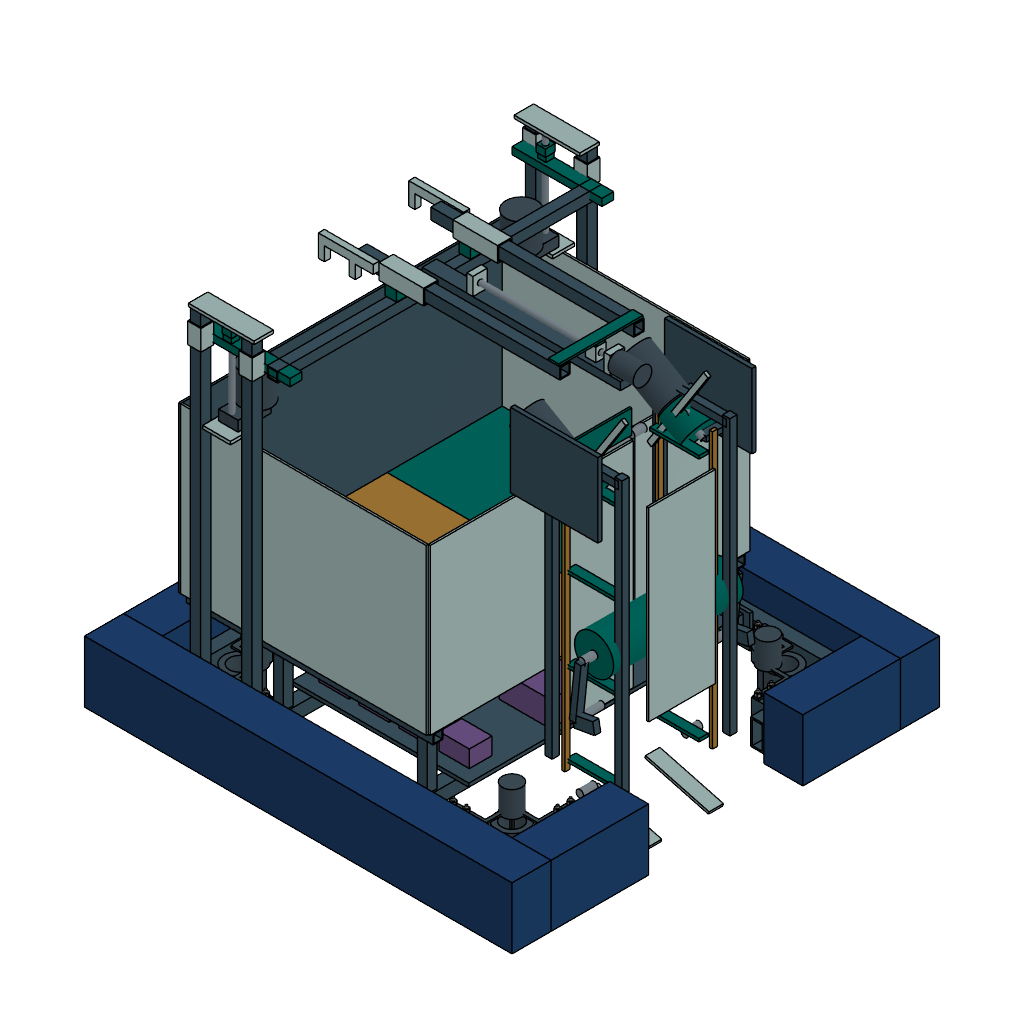
foundation-student (Autodesk Fusion 360 design; units mm, degrees)
part number: 2026-11-19-16-29-23-322
part number: 2026-11-19-16-29-24-588
part number: 2026-11-19-16-29-24-784
part number: 2026-11-19-16-29-24-907
part number: 2026-11-19-16-29-25-042
part number: 2026-11-19-16-29-25-132
part number: 2026-11-19-16-29-25-265
part number: 2026-11-19-16-29-25-401
part number: 2026-11-19-16-29-25-469
part number: 2026-11-19-16-29-25-542
part number: 2026-11-19-16-29-25-656
part number: 2026-11-19-16-29-25-749
part number: 2026-11-19-16-29-25-845
part number: 2026-11-19-16-29-25-954
part number: 2026-11-19-16-29-26-045
part number: 2026-11-19-16-29-26-140
part number: 2026-11-19-16-29-26-293
part number: 2026-11-19-16-29-26-432
part number: 2026-11-19-16-29-26-578
part number: 2026-11-19-16-29-26-718
part number: 2026-11-19-16-29-26-822
part number: 2026-11-19-16-29-26-924
part number: 2026-11-19-16-29-27-036
part number: 2026-11-19-16-29-27-164
part number: 2026-11-19-16-29-27-300
part number: 2026-11-19-16-29-27-426
part number: 2026-11-19-16-29-27-574
part number: 2026-11-19-16-29-27-708
part number: 2026-11-19-16-29-27-854
part number: 2026-11-19-16-29-28-022
part number: 2026-11-19-16-29-28-199
part number: 2026-11-19-16-29-28-361
part number: 2026-11-19-16-29-28-554
part number: 2026-11-19-16-29-28-745
part number: 2026-11-19-16-29-28-971
part number: 2026-11-19-16-29-29-160
part number: 2026-11-19-16-29-29-332
part number: 2026-11-19-16-29-29-497
part number: 2026-11-19-16-29-29-671
part number: 2026-11-19-16-29-29-862
part number: 2026-11-19-16-29-30-045
part number: 2026-11-19-16-29-30-240
part number: 2026-11-19-16-29-30-437
part number: 2026-11-19-16-29-30-622
part number: 2026-11-19-16-29-30-814
part number: 2026-11-19-16-29-30-996
part number: 2026-11-19-16-29-31-190
part number: 2026-11-19-16-29-31-381
part number: 2026-11-19-16-29-31-561
part number: 2026-11-19-16-29-31-741
part number: 2026-11-19-16-29-31-940
part number: 2026-11-19-16-29-32-174
part number: 2026-11-19-16-29-32-422
part number: 2026-11-19-16-29-32-619
part number: 2026-11-19-16-29-32-874
part number: 2026-11-19-16-29-33-099
part number: 2026-11-19-16-29-33-310
part number: 2026-11-19-16-29-33-534
part number: 2026-11-19-16-29-33-739
part number: 2026-11-19-16-29-33-957
part number: 2026-11-19-16-29-34-203
part number: 2026-11-19-16-29-34-447
part number: 2026-11-19-16-29-34-700
part number: 2026-11-19-16-29-34-969
part number: 2026-11-19-16-29-35-219
part number: 2026-11-19-16-29-35-475
part number: 2026-11-19-16-29-35-707
part number: 2026-11-19-16-29-35-952
part number: 2026-11-19-16-29-36-206
part number: 2026-11-19-16-29-36-472
part number: 2026-11-19-16-29-36-729
part number: 2026-11-19-16-29-37-001
part number: 2026-11-19-16-29-37-335
part number: 2026-11-19-16-29-37-615
part number: 2026-11-19-16-29-37-909
part number: 2026-11-19-16-29-38-228
part number: 2026-11-19-16-29-38-498
part number: 2026-11-19-16-29-38-772
part number: 2026-11-19-16-29-39-047
part number: 2026-11-19-16-29-39-326
part number: 2026-11-19-16-29-39-636
part number: 2026-11-19-16-29-40-074
part number: 2026-11-19-16-29-40-446
part number: 2026-11-19-16-29-40-762
part number: 2026-11-19-16-29-41-087
part number: 2026-11-19-16-29-41-429
part number: 2026-11-19-16-29-41-755
part number: 2026-11-19-16-29-42-071
part number: 2026-11-19-16-29-42-409
part number: 2026-11-19-16-29-42-776
part number: 2026-11-19-16-29-43-128
part number: 2026-11-19-16-29-43-473
part number: 2026-11-19-16-29-43-827
part number: 2026-11-19-16-29-44-180
part number: 2026-11-19-16-29-44-578
part number: 2026-11-19-16-29-44-987
part number: 2026-11-19-16-29-45-341
part number: 2026-11-19-16-29-45-728
part number: 2026-11-19-16-29-46-163
part number: 2026-11-19-16-29-46-577
part number: 2026-11-19-16-29-46-997
part number: 2026-11-19-16-29-47-400
part number: 2026-11-19-16-29-47-870
part number: 2026-11-19-16-29-48-379
part number: 2026-11-19-16-29-49-021
part number: 2026-11-19-16-29-49-607
part number: 2026-11-19-16-29-50-127
part number: 2026-11-19-16-29-50-624
part number: 2026-11-19-16-29-51-184
part number: 2026-11-19-16-29-51-808
part number: 2026-11-19-16-29-52-316
part number: 2026-11-19-16-29-52-811
part number: 2026-11-19-16-29-53-296
part number: 2026-11-19-16-29-53-786
part number: 2026-11-19-16-29-54-269
part number: 2026-11-19-16-29-54-713
part number: 2026-11-19-16-39-44-124
part number: 2026-11-19-16-39-44-486
part number: 2026-11-19-20-49-53-199
part number: 2026-11-19-20-49-53-588
part number: 2026-11-19-20-49-54-024
part number: 2026-11-19-20-49-54-407
part number: 2026-11-19-20-49-54-728
part number: 2026-11-19-20-49-55-064
part number: 2026-11-19-20-49-55-386
part number: 2026-11-19-20-49-55-703
part number: 2026-11-19-20-49-56-014
part number: 2026-11-19-20-49-56-330
part number: 2026-11-19-20-49-56-640
part number: 2026-11-19-20-49-56-959
part number: 2026-11-19-20-49-57-289
part number: 2026-11-19-20-49-57-613
part number: 2026-11-19-20-49-57-921
part number: 2026-11-19-20-49-58-244
part number: 2026-11-19-20-49-58-715
part number: 2026-11-19-20-49-59-050
part number: 2026-11-19-20-49-59-390
part number: 2026-11-19-20-49-59-708
part number: 2026-11-19-20-50-00-036
part number: 2026-11-19-20-50-00-368
part number: 2026-11-19-20-50-00-706
part number: 2026-11-19-20-50-01-053
part number: 2026-11-19-20-50-01-432
part number: 2026-11-19-20-50-01-806
part number: 2026-11-19-20-50-02-178
part number: 2026-11-19-20-50-02-582
part number: 2026-11-19-20-50-03-000
part number: 2026-11-19-20-50-03-410
part number: 2026-11-19-20-50-03-781
part number: 2026-11-19-20-50-04-185
part number: 2026-11-19-20-50-04-759
part number: 2026-11-19-20-50-05-171
part number: 2026-11-19-20-50-05-563
part number: 2026-11-19-20-50-05-945
part number: 2026-11-19-20-50-06-361
part number: 2026-11-19-20-50-06-774
part number: 2026-11-19-20-50-07-168
part number: 2026-11-19-20-50-07-583
part number: 2026-11-19-20-50-07-988
part number: 2026-11-19-20-50-08-402
part number: 2026-11-20-00-12-03-179
part number: 2026-11-20-00-12-05-400
part number: 2026-11-20-00-12-12-229
part number: 2026-11-20-00-12-13-884
part number: 2026-11-20-00-14-19-615
part number: 2026-11-20-00-14-22-937
part number: 2026-11-20-00-14-31-557
part number: 2026-11-20-00-14-34-829
part number: 2026-11-20-00-14-43-622
part number: 2026-11-20-00-14-52-118
part number: 2026-11-20-00-14-56-770
part number: 2026-11-20-00-15-06-271
part number: 2026-11-20-00-15-10-896
part number: 2026-11-20-00-15-14-635
part number: 2026-11-20-00-15-23-482
part number: 2026-11-20-00-15-27-004
part number: 2026-11-20-00-15-36-009
part number: 2026-11-20-00-15-45-151
part number: 2026-11-20-00-15-49-162
part number: 2026-11-20-00-15-57-500
part number: 2026-11-20-00-16-01-967
part number: 2026-11-20-00-16-05-799
part number: 2026-11-20-00-16-15-084
part number: 2026-11-20-00-16-19-187
part number: 2026-11-20-00-16-29-717
part number: 2026-11-20-00-16-41-609
part number: 2026-11-20-00-16-46-531
part number: 2026-11-20-00-16-56-596
part number: 2026-11-20-00-17-02-755
part number: 2026-11-20-00-17-07-080
part number: 2026-11-20-00-17-18-326
part number: 2026-11-20-00-17-23-572
part number: 2026-11-20-00-17-36-294
part number: 2026-11-20-00-17-48-159
part number: 2026-11-20-00-17-54-544
part number: 2026-11-20-00-18-05-921
part number: 2026-11-20-00-18-11-516
part number: 2026-11-20-00-18-15-728
part number: 2026-11-20-00-18-26-853
part number: 2026-11-20-00-18-31-111
part number: 2026-11-20-00-18-43-909
part number: 2026-11-20-00-18-56-145
part number: 2026-11-20-00-19-02-507
part number: 2026-11-20-00-19-14-913
part number: 2026-11-20-00-19-20-927
part number: 2026-11-20-00-19-26-560
part number: 2026-11-20-00-19-39-179
part number: 2026-11-20-00-19-43-997
part number: 2026-11-20-00-19-56-769
part number: 2026-11-20-00-20-10-561
part number: 2026-11-20-00-20-16-618
part number: 2026-11-20-00-20-31-020
part number: 2026-11-20-00-20-37-639
part number: 2026-11-20-00-20-43-429
part number: 2026-11-20-00-20-56-687
part number: 2026-11-20-00-21-02-006
part number: 2026-11-20-00-21-15-677
part number: 2026-11-20-00-21-30-158
part number: 2026-11-20-00-21-37-869
part number: 2026-11-20-00-21-53-268
part number: 2026-11-20-00-22-00-849
part number: 2026-11-20-00-22-06-838
part number: 2026-11-20-00-22-22-480
part number: 2026-11-20-00-22-28-660
part number: 2026-11-20-00-22-48-711
part number: 2026-11-20-00-23-07-970
part number: 2026-11-20-00-23-16-941
part number: 2026-11-20-00-23-37-375
part number: 2026-11-20-00-25-41-586
part number: 2026-11-20-00-26-13-050
part number: 2026-11-20-00-28-41-417
part number: 2026-11-20-00-29-10-943
part number: 2026-11-20-00-32-07-156
part number: 2026-11-20-00-32-46-030
part number: 2026-11-20-00-35-42-419
part number: 2026-11-20-00-36-22-594
Autodesk Fusion 360 part; units mm, degrees
(part 1 of 7)
sketch "Editable cross section" plane through (0, 0, 0) normal (0, 0, 1) x (1, 0, 0) in component "left perimeter tube"
  line L0 (-12.7, -25.4) -> (12.7, -25.4)
  line L1 (12.7, -25.4) -> (12.7, 25.4)
  line L2 (12.7, 25.4) -> (-12.7, 25.4)
  line L3 (-12.7, 25.4) -> (-12.7, -25.4)
  line L4 (-10.16, -22.86) -> (10.16, -22.86)
  line L5 (10.16, -22.86) -> (10.16, 22.86)
  line L6 (10.16, 22.86) -> (-10.16, 22.86)
  line L7 (-10.16, 22.86) -> (-10.16, -22.86)
sketch "Editable cross section (2)" plane through (0, 0, 0) normal (0, 0, 1) x (1, 0, 0) in component "left front return"
  line L0 (-12.7, -25.4) -> (12.7, -25.4)
  line L1 (12.7, -25.4) -> (12.7, 25.4)
  line L2 (12.7, 25.4) -> (-12.7, 25.4)
  line L3 (-12.7, 25.4) -> (-12.7, -25.4)
  line L4 (-10.16, -22.86) -> (10.16, -22.86)
  line L5 (10.16, -22.86) -> (10.16, 22.86)
  line L6 (10.16, 22.86) -> (-10.16, 22.86)
  line L7 (-10.16, 22.86) -> (-10.16, -22.86)
sketch "Editable cross section (3)" plane through (0, 0, 0) normal (0, 0, 1) x (1, 0, 0) in component "left blue side bumper"
  line L0 (-416, -38) -> (416, -38)
  line L1 (416, -38) -> (416, 38)
  line L2 (416, 38) -> (-416, 38)
  line L3 (-416, 38) -> (-416, -38)
extrude "Stock length" add sketch "Editable cross section (3)" along normal blind 120 makes body 1 in component "left blue side bumper"
sketch "Editable cross section (4)" plane through (0, 0, 0) normal (0, 0, 1) x (1, 0, 0) in component "left blue front bumper"
  line L0 (-38, -95) -> (38, -95)
  line L1 (38, -95) -> (38, 95)
  line L2 (38, 95) -> (-38, 95)
  line L3 (-38, 95) -> (-38, -95)
extrude "Stock length'" add sketch "Editable cross section (4)" along normal blind 120 separate body makes body 2 in component "left blue front bumper"
sketch "Editable cross section (5)" plane through (0, 0, 0) normal (0, 0, 1) x (1, 0, 0) in component "right perimeter tube"
  line L0 (-12.7, -25.4) -> (12.7, -25.4)
  line L1 (12.7, -25.4) -> (12.7, 25.4)
  line L2 (12.7, 25.4) -> (-12.7, 25.4)
  line L3 (-12.7, 25.4) -> (-12.7, -25.4)
  line L4 (-10.16, -22.86) -> (10.16, -22.86)
  line L5 (10.16, -22.86) -> (10.16, 22.86)
  line L6 (10.16, 22.86) -> (-10.16, 22.86)
  line L7 (-10.16, 22.86) -> (-10.16, -22.86)
sketch "Editable cross section (6)" plane through (0, 0, 0) normal (0, 0, 1) x (1, 0, 0) in component "right front return"
  line L0 (-12.7, -25.4) -> (12.7, -25.4)
  line L1 (12.7, -25.4) -> (12.7, 25.4)
  line L2 (12.7, 25.4) -> (-12.7, 25.4)
  line L3 (-12.7, 25.4) -> (-12.7, -25.4)
  line L4 (-10.16, -22.86) -> (10.16, -22.86)
  line L5 (10.16, -22.86) -> (10.16, 22.86)
  line L6 (10.16, 22.86) -> (-10.16, 22.86)
  line L7 (-10.16, 22.86) -> (-10.16, -22.86)
sketch "Editable cross section (7)" plane through (0, 0, 0) normal (0, 0, 1) x (1, 0, 0) in component "right blue side bumper"
  line L0 (-416, -38) -> (416, -38)
  line L1 (416, -38) -> (416, 38)
  line L2 (416, 38) -> (-416, 38)
  line L3 (-416, 38) -> (-416, -38)
extrude "Stock length''" add sketch "Editable cross section (7)" along normal blind 120 separate body makes body 3 in component "right blue side bumper"
sketch "Editable cross section (8)" plane through (0, 0, 0) normal (0, 0, 1) x (1, 0, 0) in component "right blue front bumper"
  line L0 (-38, -95) -> (38, -95)
  line L1 (38, -95) -> (38, 95)
  line L2 (38, 95) -> (-38, 95)
  line L3 (-38, 95) -> (-38, -95)
extrude "Stock length'''" add sketch "Editable cross section (8)" along normal blind 120 separate body makes body 4 in component "right blue front bumper"
sketch "Editable cross section (9)" plane through (0, 0, 0) normal (0, 0, 1) x (1, 0, 0) in component "rear perimeter tube"
  line L0 (-12.7, -25.4) -> (12.7, -25.4)
  line L1 (12.7, -25.4) -> (12.7, 25.4)
  line L2 (12.7, 25.4) -> (-12.7, 25.4)
  line L3 (-12.7, 25.4) -> (-12.7, -25.4)
  line L4 (-10.16, -22.86) -> (10.16, -22.86)
  line L5 (10.16, -22.86) -> (10.16, 22.86)
  line L6 (10.16, 22.86) -> (-10.16, 22.86)
  line L7 (-10.16, 22.86) -> (-10.16, -22.86)
sketch "Editable cross section (10)" plane through (0, 0, 0) normal (0, 0, 1) x (1, 0, 0) in component "rear blue bumper"
  line L0 (-38, -340) -> (38, -340)
  line L1 (38, -340) -> (38, 340)
  line L2 (38, 340) -> (-38, 340)
  line L3 (-38, 340) -> (-38, -340)
extrude "Stock length''''" add sketch "Editable cross section (10)" along normal blind 120 separate body makes body 5 in component "rear blue bumper"
sketch "Editable cross section (11)" plane through (0, 0, 0) normal (0, 0, 1) x (1, 0, 0) in component "front left module tab spacer 1"
  line L0 (-18.5, -11.55) -> (18.5, -11.55)
  line L1 (18.5, -11.55) -> (18.5, 11.55)
  line L2 (18.5, 11.55) -> (-18.5, 11.55)
  line L3 (-18.5, 11.55) -> (-18.5, -11.55)
  circle A0 centre (12.85, -3.3) radius 2.65
  circle A1 centre (-12.55, -3.3) radius 2.65
sketch "Editable cross section (12)" plane through (0, 0, 0) normal (0, 0, 1) x (1, 0, 0) in component "front left module tab spacer 2"
  line L0 (-11.55, -18.5) -> (11.55, -18.5)
  line L1 (11.55, -18.5) -> (11.55, 18.5)
  line L2 (11.55, 18.5) -> (-11.55, 18.5)
  line L3 (-11.55, 18.5) -> (-11.55, -18.5)
  circle A0 centre (-3.3, 12.85) radius 2.65
  circle A1 centre (-3.3, -12.55) radius 2.65
sketch "Editable cross section (13)" plane through (0, 0, 0) normal (0, 0, 1) x (1, 0, 0) in component "front right module tab spacer 1"
  line L0 (-11.55, -18.5) -> (11.55, -18.5)
  line L1 (11.55, -18.5) -> (11.55, 18.5)
  line L2 (11.55, 18.5) -> (-11.55, 18.5)
  line L3 (-11.55, 18.5) -> (-11.55, -18.5)
  circle A0 centre (-3.3, -12.85) radius 2.65
  circle A1 centre (-3.3, 12.55) radius 2.65
sketch "Editable cross section (14)" plane through (0, 0, 0) normal (0, 0, 1) x (1, 0, 0) in component "front right module tab spacer 2"
  line L0 (-18.5, -11.55) -> (18.5, -11.55)
  line L1 (18.5, -11.55) -> (18.5, 11.55)
  line L2 (18.5, 11.55) -> (-18.5, 11.55)
  line L3 (-18.5, 11.55) -> (-18.5, -11.55)
  circle A0 centre (12.85, 3.3) radius 2.65
  circle A1 centre (-12.55, 3.3) radius 2.65
sketch "Editable cross section (15)" plane through (0, 0, 0) normal (0, 0, 1) x (1, 0, 0) in component "rear left module tab spacer 1"
  line L0 (-11.55, -18.5) -> (11.55, -18.5)
  line L1 (11.55, -18.5) -> (11.55, 18.5)
  line L2 (11.55, 18.5) -> (-11.55, 18.5)
  line L3 (-11.55, 18.5) -> (-11.55, -18.5)
  circle A0 centre (3.3, 12.85) radius 2.65
  circle A1 centre (3.3, -12.55) radius 2.65
sketch "Editable cross section (16)" plane through (0, 0, 0) normal (0, 0, 1) x (1, 0, 0) in component "rear left module tab spacer 2"
  line L0 (-18.5, -11.55) -> (18.5, -11.55)
  line L1 (18.5, -11.55) -> (18.5, 11.55)
  line L2 (18.5, 11.55) -> (-18.5, 11.55)
  line L3 (-18.5, 11.55) -> (-18.5, -11.55)
  circle A0 centre (-12.85, -3.3) radius 2.65
  circle A1 centre (12.55, -3.3) radius 2.65
sketch "Editable cross section (17)" plane through (0, 0, 0) normal (0, 0, 1) x (1, 0, 0) in component "rear right module tab spacer 1"
  line L0 (-18.5, -11.55) -> (18.5, -11.55)
  line L1 (18.5, -11.55) -> (18.5, 11.55)
  line L2 (18.5, 11.55) -> (-18.5, 11.55)
  line L3 (-18.5, 11.55) -> (-18.5, -11.55)
  circle A0 centre (-12.85, 3.3) radius 2.65
  circle A1 centre (12.55, 3.3) radius 2.65
sketch "Editable cross section (18)" plane through (0, 0, 0) normal (0, 0, 1) x (1, 0, 0) in component "rear right module tab spacer 2"
  line L0 (-11.55, -18.5) -> (11.55, -18.5)
  line L1 (11.55, -18.5) -> (11.55, 18.5)
  line L2 (11.55, 18.5) -> (-11.55, 18.5)
  line L3 (-11.55, 18.5) -> (-11.55, -18.5)
  circle A0 centre (3.3, -12.85) radius 2.65
  circle A1 centre (3.3, 12.55) radius 2.65
sketch "Editable cross section (19)" plane through (0, 0, 0) normal (0, 0, 1) x (1, 0, 0) in component "rear right hopper post"
  line L0 (-10, -8) -> (10, -8)
  line L1 (10, -8) -> (10, 8)
  line L2 (10, 8) -> (-10, 8)
  line L3 (-10, 8) -> (-10, -8)
sketch "Editable cross section (20)" plane through (0, 0, 0) normal (0, 0, 1) x (1, 0, 0) in component "front right hopper post"
  line L0 (-10, -8) -> (10, -8)
  line L1 (10, -8) -> (10, 8)
  line L2 (10, 8) -> (-10, 8)
  line L3 (-10, 8) -> (-10, -8)
sketch "Editable cross section (21)" plane through (0, 0, 0) normal (0, 0, 1) x (1, 0, 0) in component "right floor sill"
  line L0 (-9, -6) -> (9, -6)
  line L1 (9, -6) -> (9, 6)
  line L2 (9, 6) -> (-9, 6)
  line L3 (-9, 6) -> (-9, -6)
sketch "Editable cross section (22)" plane through (0, 0, 0) normal (0, 0, 1) x (1, 0, 0) in component "rear left hopper post"
  line L0 (-10, -8) -> (10, -8)
  line L1 (10, -8) -> (10, 8)
  line L2 (10, 8) -> (-10, 8)
  line L3 (-10, 8) -> (-10, -8)
sketch "Editable cross section (23)" plane through (0, 0, 0) normal (0, 0, 1) x (1, 0, 0) in component "front left hopper post"
  line L0 (-10, -8) -> (10, -8)
  line L1 (10, -8) -> (10, 8)
  line L2 (10, 8) -> (-10, 8)
  line L3 (-10, 8) -> (-10, -8)
sketch "Editable cross section (24)" plane through (0, 0, 0) normal (0, 0, 1) x (1, 0, 0) in component "left floor sill"
  line L0 (-9, -6) -> (9, -6)
  line L1 (9, -6) -> (9, 6)
  line L2 (9, 6) -> (-9, 6)
  line L3 (-9, 6) -> (-9, -6)
sketch "Editable cross section (25)" plane through (0, 0, 0) normal (0, 0, 1) x (1, 0, 0) in component "rear deck crossmember"
  line L0 (-10, -12.5) -> (10, -12.5)
  line L1 (10, -12.5) -> (10, 12.5)
  line L2 (10, 12.5) -> (-10, 12.5)
  line L3 (-10, 12.5) -> (-10, -12.5)
sketch "Editable cross section (26)" plane through (0, 0, 0) normal (0, 0, 1) x (1, 0, 0) in component "front deck crossmember"
  line L0 (-10, -12.5) -> (10, -12.5)
  line L1 (10, -12.5) -> (10, 12.5)
  line L2 (10, 12.5) -> (-10, 12.5)
  line L3 (-10, 12.5) -> (-10, -12.5)
sketch "Editable cross section (27)" plane through (0, 0, 0) normal (0, 0, 1) x (1, 0, 0) in component "left electronics deck"
  line L0 (-172.5, -102) -> (172.5, -102)
  line L1 (172.5, -102) -> (172.5, 102)
  line L2 (172.5, 102) -> (-172.5, 102)
  line L3 (-172.5, 102) -> (-172.5, -102)
extrude "Stock length'''''" add sketch "Editable cross section (27)" along normal blind 7 separate body makes body 6 in component "left electronics deck"
sketch "Editable cross section (28)" plane through (0, 0, 0) normal (0, 0, 1) x (1, 0, 0) in component "right electronics deck"
  line L0 (-172.5, -103.5) -> (172.5, -103.5)
  line L1 (172.5, -103.5) -> (172.5, 103.5)
  line L2 (172.5, 103.5) -> (-172.5, 103.5)
  line L3 (-172.5, 103.5) -> (-172.5, -103.5)
extrude "Stock length''''''" add sketch "Editable cross section (28)" along normal blind 7 separate body makes body 7 in component "right electronics deck"
sketch "Editable cross section (29)" plane through (0, 0, 0) normal (0, 0, 1) x (1, 0, 0) in component "fore electronics deck bridge"
  line L0 (-56.5, -45.5) -> (56.5, -45.5)
  line L1 (56.5, -45.5) -> (56.5, 45.5)
  line L2 (56.5, 45.5) -> (-56.5, 45.5)
  line L3 (-56.5, 45.5) -> (-56.5, -45.5)
extrude "Stock length'''''''" add sketch "Editable cross section (29)" along normal blind 7 separate body makes body 8 in component "fore electronics deck bridge"
sketch "Editable cross section (30)" plane through (0, 0, 0) normal (0, 0, 1) x (1, 0, 0) in component "aft electronics deck bridge"
  line L0 (-20.5, -45.5) -> (20.5, -45.5)
  line L1 (20.5, -45.5) -> (20.5, 45.5)
  line L2 (20.5, 45.5) -> (-20.5, 45.5)
  line L3 (-20.5, 45.5) -> (-20.5, -45.5)
extrude "Stock length''''''''" add sketch "Editable cross section (30)" along normal blind 7 separate body makes body 9 in component "aft electronics deck bridge"
sketch "Editable cross section (31)" plane through (0, 0, 0) normal (0, 0, 1) x (1, 0, 0) in component "battery cradle floor"
  line L0 (-95.5, -45.5) -> (95.5, -45.5)
  line L1 (95.5, -45.5) -> (95.5, 45.5)
  line L2 (95.5, 45.5) -> (-95.5, 45.5)
  line L3 (-95.5, 45.5) -> (-95.5, -45.5)
extrude "Stock length'''''''''" add sketch "Editable cross section (31)" along normal blind 4 separate body makes body 10 in component "battery cradle floor"
sketch "Editable cross section (32)" plane through (0, 0, 0) normal (0, 0, 1) x (1, 0, 0) in component "battery cradle wall -44"
  line L0 (-95.5, -2) -> (95.5, -2)
  line L1 (95.5, -2) -> (95.5, 2)
  line L2 (95.5, 2) -> (-95.5, 2)
  line L3 (-95.5, 2) -> (-95.5, -2)
extrude "Stock length''''''''''" add sketch "Editable cross section (32)" along normal blind 81 separate body makes body 11 in component "battery cradle wall -44"
sketch "Editable cross section (33)" plane through (0, 0, 0) normal (0, 0, 1) x (1, 0, 0) in component "battery cradle wall 43"
  line L0 (-95.5, -2) -> (95.5, -2)
  line L1 (95.5, -2) -> (95.5, 2)
  line L2 (95.5, 2) -> (-95.5, 2)
  line L3 (-95.5, 2) -> (-95.5, -2)
extrude "Stock length'''''''''''" add sketch "Editable cross section (33)" along normal blind 81 separate body makes body 12 in component "battery cradle wall 43"
sketch "Editable cross section (34)" plane through (0, 0, 0) normal (0, 0, 1) x (1, 0, 0) in component "battery secured envelope"
  line L0 (-90.5, -38) -> (90.5, -38)
  line L1 (90.5, -38) -> (90.5, 38)
  line L2 (90.5, 38) -> (-90.5, 38)
  line L3 (-90.5, 38) -> (-90.5, -38)
extrude "Stock length''''''''''''" add sketch "Editable cross section (34)" along normal blind 167 separate body makes body 13 in component "battery secured envelope"
sketch "Editable cross section (35)" plane through (0, 0, 0) normal (0, 0, 1) x (1, 0, 0) in component "distribution enclosure reserve"
  line L0 (-50, -77) -> (50, -77)
  line L1 (50, -77) -> (50, 77)
  line L2 (50, 77) -> (-50, 77)
  line L3 (-50, 77) -> (-50, -77)
extrude "Stock length'''''''''''''" add sketch "Editable cross section (35)" along normal blind 49 separate body makes body 14 in component "distribution enclosure reserve"
sketch "Editable cross section (36)" plane through (0, 0, 0) normal (0, 0, 1) x (1, 0, 0) in component "robot controller reserve"
  line L0 (-83.5, -46) -> (83.5, -46)
  line L1 (83.5, -46) -> (83.5, 46)
  line L2 (83.5, 46) -> (-83.5, 46)
  line L3 (-83.5, 46) -> (-83.5, -46)
extrude "Stock length''''''''''''''" add sketch "Editable cross section (36)" along normal blind 42 separate body makes body 15 in component "robot controller reserve"
sketch "Editable cross section (37)" plane through (0, 0, 0) normal (0, 0, 1) x (1, 0, 0) in component "field radio reserve"
  line L0 (-64.5, -36.5) -> (64.5, -36.5)
  line L1 (64.5, -36.5) -> (64.5, 36.5)
  line L2 (64.5, 36.5) -> (-64.5, 36.5)
  line L3 (-64.5, 36.5) -> (-64.5, -36.5)
extrude "Stock length'''''''''''''''" add sketch "Editable cross section (37)" along normal blind 39 separate body makes body 16 in component "field radio reserve"
sketch "Editable cross section (38)" plane through (0, 0, 0) normal (0, 0, 1) x (1, 0, 0) in component "drive controller reserve 1"
  line L0 (-29.5, -22) -> (29.5, -22)
  line L1 (29.5, -22) -> (29.5, 22)
  line L2 (29.5, 22) -> (-29.5, 22)
  line L3 (-29.5, 22) -> (-29.5, -22)
extrude "Stock length''''''''''''''''" add sketch "Editable cross section (38)" along normal blind 33 separate body makes body 17 in component "drive controller reserve 1"
sketch "Editable cross section (39)" plane through (0, 0, 0) normal (0, 0, 1) x (1, 0, 0) in component "drive controller reserve 2"
  line L0 (-29.5, -22) -> (29.5, -22)
  line L1 (29.5, -22) -> (29.5, 22)
  line L2 (29.5, 22) -> (-29.5, 22)
  line L3 (-29.5, 22) -> (-29.5, -22)
extrude "Stock length'''''''''''''''''" add sketch "Editable cross section (39)" along normal blind 33 separate body makes body 18 in component "drive controller reserve 2"
sketch "Editable cross section (40)" plane through (0, 0, 0) normal (0, 0, 1) x (1, 0, 0) in component "drive controller reserve 3"
  line L0 (-29.5, -22) -> (29.5, -22)
  line L1 (29.5, -22) -> (29.5, 22)
  line L2 (29.5, 22) -> (-29.5, 22)
  line L3 (-29.5, 22) -> (-29.5, -22)
extrude "Stock length''''''''''''''''''" add sketch "Editable cross section (40)" along normal blind 33 separate body makes body 19 in component "drive controller reserve 3"
sketch "Editable cross section (41)" plane through (0, 0, 0) normal (0, 0, 1) x (1, 0, 0) in component "drive controller reserve 4"
  line L0 (-29.5, -22) -> (29.5, -22)
  line L1 (29.5, -22) -> (29.5, 22)
  line L2 (29.5, 22) -> (-29.5, 22)
  line L3 (-29.5, 22) -> (-29.5, -22)
extrude "Stock length'''''''''''''''''''" add sketch "Editable cross section (41)" along normal blind 33 separate body makes body 20 in component "drive controller reserve 4"
sketch "Editable cross section (42)" plane through (0, 0, 0) normal (0, 0, 1) x (1, 0, 0) in component "drive controller reserve 5"
  line L0 (-29.5, -22) -> (29.5, -22)
  line L1 (29.5, -22) -> (29.5, 22)
  line L2 (29.5, 22) -> (-29.5, 22)
  line L3 (-29.5, 22) -> (-29.5, -22)
extrude "Stock length''''''''''''''''''''" add sketch "Editable cross section (42)" along normal blind 33 separate body makes body 21 in component "drive controller reserve 5"
sketch "Editable cross section (43)" plane through (0, 0, 0) normal (0, 0, 1) x (1, 0, 0) in component "drive controller reserve 6"
  line L0 (-29.5, -22) -> (29.5, -22)
  line L1 (29.5, -22) -> (29.5, 22)
  line L2 (29.5, 22) -> (-29.5, 22)
  line L3 (-29.5, 22) -> (-29.5, -22)
extrude "Stock length'''''''''''''''''''''" add sketch "Editable cross section (43)" along normal blind 33 separate body makes body 22 in component "drive controller reserve 6"
sketch "Editable cross section (44)" plane through (0, 0, 0) normal (0, 0, 1) x (1, 0, 0) in component "drive controller reserve 7"
  line L0 (-29.5, -22) -> (29.5, -22)
  line L1 (29.5, -22) -> (29.5, 22)
  line L2 (29.5, 22) -> (-29.5, 22)
  line L3 (-29.5, 22) -> (-29.5, -22)
extrude "Stock length''''''''''''''''''''''" add sketch "Editable cross section (44)" along normal blind 33 separate body makes body 23 in component "drive controller reserve 7"
sketch "Editable cross section (45)" plane through (0, 0, 0) normal (0, 0, 1) x (1, 0, 0) in component "drive controller reserve 8"
  line L0 (-29.5, -22) -> (29.5, -22)
  line L1 (29.5, -22) -> (29.5, 22)
  line L2 (29.5, 22) -> (-29.5, 22)
  line L3 (-29.5, 22) -> (-29.5, -22)
extrude "Stock length'''''''''''''''''''''''" add sketch "Editable cross section (45)" along normal blind 33 separate body makes body 24 in component "drive controller reserve 8"
sketch "Editable cross section (46)" plane through (0, 0, 0) normal (0, 0, 1) x (1, 0, 0) in component "hopper back panel"
  line L0 (-2, -315) -> (2, -315)
  line L1 (2, -315) -> (2, 315)
  line L2 (2, 315) -> (-2, 315)
  line L3 (-2, 315) -> (-2, -315)
extrude "Stock length''''''''''''''''''''''''" add sketch "Editable cross section (46)" along normal blind 320 separate body makes body 25 in component "hopper back panel"
sketch "Editable cross section (47)" plane through (0, 0, 0) normal (0, 0, 1) x (1, 0, 0) in component "right hopper wall"
  line L0 (-239, -2) -> (239, -2)
  line L1 (239, -2) -> (239, 2)
  line L2 (239, 2) -> (-239, 2)
  line L3 (-239, 2) -> (-239, -2)
extrude "Stock length'''''''''''''''''''''''''" add sketch "Editable cross section (47)" along normal blind 320 separate body makes body 26 in component "right hopper wall"
sketch "Editable cross section (48)" plane through (0, 0, 0) normal (0, 0, 1) x (1, 0, 0) in component "right hopper front wing"
  line L0 (-2, -112) -> (2, -112)
  line L1 (2, -112) -> (2, 112)
  line L2 (2, 112) -> (-2, 112)
  line L3 (-2, 112) -> (-2, -112)
extrude "Stock length''''''''''''''''''''''''''" add sketch "Editable cross section (48)" along normal blind 320 separate body makes body 27 in component "right hopper front wing"
sketch "Editable cross section (49)" plane through (0, 0, 0) normal (0, 0, 1) x (1, 0, 0) in component "right cross feed deck"
  line L0 (-239, -112) -> (239, -112)
  line L1 (239, -112) -> (239, 112)
  line L2 (239, 112) -> (-239, 112)
  line L3 (-239, 112) -> (-239, -112)
extrude "Stock length'''''''''''''''''''''''''''" add sketch "Editable cross section (49)" along normal blind 5 separate body makes body 28 in component "right cross feed deck"
sketch "Editable cross section (50)" plane through (0, 0, 0) normal (0, 0, 1) x (1, 0, 0) in component "right front elevator upright"
  line L0 (-7, -7) -> (7, -7)
  line L1 (7, -7) -> (7, 7)
  line L2 (7, 7) -> (-7, 7)
  line L3 (-7, 7) -> (-7, -7)
extrude "Stock length''''''''''''''''''''''''''''" add sketch "Editable cross section (50)" along normal blind 537 separate body makes body 29 in component "right front elevator upright"
sketch "Editable cross section (51)" plane through (0, 0, 0) normal (0, 0, 1) x (1, 0, 0) in component "right rear elevator upright"
  line L0 (-7, -7) -> (7, -7)
  line L1 (7, -7) -> (7, 7)
  line L2 (7, 7) -> (-7, 7)
  line L3 (-7, 7) -> (-7, -7)
extrude "Stock length'''''''''''''''''''''''''''''" add sketch "Editable cross section (51)" along normal blind 535 separate body makes body 30 in component "right rear elevator upright"
sketch "Editable cross section (52)" plane through (0, 0, 0) normal (0, 0, 1) x (1, 0, 0) in component "right elevator upper tie"
  line L0 (-7, -7) -> (7, -7)
  line L1 (7, -7) -> (7, 7)
  line L2 (7, 7) -> (-7, 7)
  line L3 (-7, 7) -> (-7, -7)
extrude "Stock length''''''''''''''''''''''''''''''" add sketch "Editable cross section (52)" along normal blind 138 separate body makes body 31 in component "right elevator upper tie"
sketch "Editable cross section (53)" plane through (0, 0, 0) normal (0, 0, 1) x (1, 0, 0) in component "right inside lift belt"
  line L0 (-3, -5) -> (3, -5)
  line L1 (3, -5) -> (3, 5)
  line L2 (3, 5) -> (-3, 5)
  line L3 (-3, 5) -> (-3, -5)
extrude "Stock length'''''''''''''''''''''''''''''''" add sketch "Editable cross section (53)" along normal blind 535 separate body makes body 32 in component "right inside lift belt"
sketch "Editable cross section (54)" plane through (0, 0, 0) normal (0, 0, 1) x (1, 0, 0) in component "right outside lift belt"
  line L0 (-3, -5) -> (3, -5)
  line L1 (3, -5) -> (3, 5)
  line L2 (3, 5) -> (-3, 5)
  line L3 (-3, 5) -> (-3, -5)
extrude "Stock length''''''''''''''''''''''''''''''''" add sketch "Editable cross section (54)" along normal blind 535 separate body makes body 33 in component "right outside lift belt"
sketch "Editable cross section (55)" plane through (0, 0, 0) normal (0, 0, 1) x (1, 0, 0) in component "right lift shelf 1"
  line L0 (-48, -9) -> (48, -9)
  line L1 (48, -9) -> (48, 9)
  line L2 (48, 9) -> (-48, 9)
  line L3 (-48, 9) -> (-48, -9)
extrude "Stock length'''''''''''''''''''''''''''''''''" add sketch "Editable cross section (55)" along normal blind 6 separate body makes body 34 in component "right lift shelf 1"
sketch "Editable cross section (56)" plane through (0, 0, 0) normal (0, 0, 1) x (1, 0, 0) in component "right lift shelf 2"
  line L0 (-48, -9) -> (48, -9)
  line L1 (48, -9) -> (48, 9)
  line L2 (48, 9) -> (-48, 9)
  line L3 (-48, 9) -> (-48, -9)
extrude "Stock length''''''''''''''''''''''''''''''''''" add sketch "Editable cross section (56)" along normal blind 6 separate body makes body 35 in component "right lift shelf 2"
sketch "Editable cross section (57)" plane through (0, 0, 0) normal (0, 0, 1) x (1, 0, 0) in component "right lift shelf 3"
  line L0 (-48, -9) -> (48, -9)
  line L1 (48, -9) -> (48, 9)
  line L2 (48, 9) -> (-48, 9)
  line L3 (-48, 9) -> (-48, -9)
extrude "Stock length'''''''''''''''''''''''''''''''''''" add sketch "Editable cross section (57)" along normal blind 6 separate body makes body 36 in component "right lift shelf 3"
sketch "Editable cross section (58)" plane through (0, 0, 0) normal (0, 0, 1) x (1, 0, 0) in component "right lift shelf 4"
  line L0 (-48, -9) -> (48, -9)
  line L1 (48, -9) -> (48, 9)
  line L2 (48, 9) -> (-48, 9)
  line L3 (-48, 9) -> (-48, -9)
extrude "Stock length''''''''''''''''''''''''''''''''''''" add sketch "Editable cross section (58)" along normal blind 6 separate body makes body 37 in component "right lift shelf 4"
sketch "Editable cross section (59)" plane through (0, 0, 0) normal (0, 0, 1) x (1, 0, 0) in component "right intake ramp"
  line L0 (-14, -2.5) -> (14, -2.5)
  line L1 (14, -2.5) -> (14, 2.5)
  line L2 (14, 2.5) -> (-14, 2.5)
  line L3 (-14, 2.5) -> (-14, -2.5)
extrude "Stock length'''''''''''''''''''''''''''''''''''''" add sketch "Editable cross section (59)" along normal blind 128.316 separate body makes body 38 in component "right intake ramp"
sketch "Editable cross section (60)" plane through (0, 0, 0) normal (0, 0, 1) x (1, 0, 0) in component "left hopper wall"
  line L0 (-239, -2) -> (239, -2)
  line L1 (239, -2) -> (239, 2)
  line L2 (239, 2) -> (-239, 2)
  line L3 (-239, 2) -> (-239, -2)
extrude "Stock length''''''''''''''''''''''''''''''''''''''" add sketch "Editable cross section (60)" along normal blind 320 separate body makes body 39 in component "left hopper wall"
sketch "Editable cross section (61)" plane through (0, 0, 0) normal (0, 0, 1) x (1, 0, 0) in component "left hopper front wing"
  line L0 (-2, -112) -> (2, -112)
  line L1 (2, -112) -> (2, 112)
  line L2 (2, 112) -> (-2, 112)
  line L3 (-2, 112) -> (-2, -112)
extrude "Stock length'''''''''''''''''''''''''''''''''''''''" add sketch "Editable cross section (61)" along normal blind 320 separate body makes body 40 in component "left hopper front wing"
sketch "Editable cross section (62)" plane through (0, 0, 0) normal (0, 0, 1) x (1, 0, 0) in component "left cross feed deck"
  line L0 (-239, -112) -> (239, -112)
  line L1 (239, -112) -> (239, 112)
  line L2 (239, 112) -> (-239, 112)
  line L3 (-239, 112) -> (-239, -112)
extrude "Stock length''''''''''''''''''''''''''''''''''''''''" add sketch "Editable cross section (62)" along normal blind 5 separate body makes body 41 in component "left cross feed deck"
sketch "Editable cross section (63)" plane through (0, 0, 0) normal (0, 0, 1) x (1, 0, 0) in component "left front elevator upright"
  line L0 (-7, -7) -> (7, -7)
  line L1 (7, -7) -> (7, 7)
  line L2 (7, 7) -> (-7, 7)
  line L3 (-7, 7) -> (-7, -7)
extrude "Stock length'''''''''''''''''''''''''''''''''''''''''" add sketch "Editable cross section (63)" along normal blind 537 separate body makes body 42 in component "left front elevator upright"
sketch "Editable cross section (64)" plane through (0, 0, 0) normal (0, 0, 1) x (1, 0, 0) in component "left rear elevator upright"
  line L0 (-7, -7) -> (7, -7)
  line L1 (7, -7) -> (7, 7)
  line L2 (7, 7) -> (-7, 7)
  line L3 (-7, 7) -> (-7, -7)
extrude "Stock length''''''''''''''''''''''''''''''''''''''''''" add sketch "Editable cross section (64)" along normal blind 535 separate body makes body 43 in component "left rear elevator upright"
sketch "Editable cross section (65)" plane through (0, 0, 0) normal (0, 0, 1) x (1, 0, 0) in component "left elevator upper tie"
  line L0 (-7, -7) -> (7, -7)
  line L1 (7, -7) -> (7, 7)
  line L2 (7, 7) -> (-7, 7)
  line L3 (-7, 7) -> (-7, -7)
extrude "Stock length'''''''''''''''''''''''''''''''''''''''''''" add sketch "Editable cross section (65)" along normal blind 138 separate body makes body 44 in component "left elevator upper tie"
sketch "Editable cross section (66)" plane through (0, 0, 0) normal (0, 0, 1) x (1, 0, 0) in component "left inside lift belt"
  line L0 (-3, -5) -> (3, -5)
  line L1 (3, -5) -> (3, 5)
  line L2 (3, 5) -> (-3, 5)
  line L3 (-3, 5) -> (-3, -5)
extrude "Stock length''''''''''''''''''''''''''''''''''''''''''''" add sketch "Editable cross section (66)" along normal blind 535 separate body makes body 45 in component "left inside lift belt"
sketch "Editable cross section (67)" plane through (0, 0, 0) normal (0, 0, 1) x (1, 0, 0) in component "left outside lift belt"
  line L0 (-3, -5) -> (3, -5)
  line L1 (3, -5) -> (3, 5)
  line L2 (3, 5) -> (-3, 5)
  line L3 (-3, 5) -> (-3, -5)
extrude "Stock length'''''''''''''''''''''''''''''''''''''''''''''" add sketch "Editable cross section (67)" along normal blind 535 separate body makes body 46 in component "left outside lift belt"
sketch "Editable cross section (68)" plane through (0, 0, 0) normal (0, 0, 1) x (1, 0, 0) in component "left lift shelf 1"
  line L0 (-48, -9) -> (48, -9)
  line L1 (48, -9) -> (48, 9)
  line L2 (48, 9) -> (-48, 9)
  line L3 (-48, 9) -> (-48, -9)
extrude "Stock length''''''''''''''''''''''''''''''''''''''''''''''" add sketch "Editable cross section (68)" along normal blind 6 separate body makes body 47 in component "left lift shelf 1"
sketch "Editable cross section (69)" plane through (0, 0, 0) normal (0, 0, 1) x (1, 0, 0) in component "left lift shelf 2"
  line L0 (-48, -9) -> (48, -9)
  line L1 (48, -9) -> (48, 9)
  line L2 (48, 9) -> (-48, 9)
  line L3 (-48, 9) -> (-48, -9)
extrude "Stock length'''''''''''''''''''''''''''''''''''''''''''''''" add sketch "Editable cross section (69)" along normal blind 6 separate body makes body 48 in component "left lift shelf 2"
sketch "Editable cross section (70)" plane through (0, 0, 0) normal (0, 0, 1) x (1, 0, 0) in component "left lift shelf 3"
  line L0 (-48, -9) -> (48, -9)
  line L1 (48, -9) -> (48, 9)
  line L2 (48, 9) -> (-48, 9)
  line L3 (-48, 9) -> (-48, -9)
extrude "Stock length''''''''''''''''''''''''''''''''''''''''''''''''" add sketch "Editable cross section (70)" along normal blind 6 separate body makes body 49 in component "left lift shelf 3"
sketch "Editable cross section (71)" plane through (0, 0, 0) normal (0, 0, 1) x (1, 0, 0) in component "left lift shelf 4"
  line L0 (-48, -9) -> (48, -9)
  line L1 (48, -9) -> (48, 9)
  line L2 (48, 9) -> (-48, 9)
  line L3 (-48, 9) -> (-48, -9)
extrude "Stock length'''''''''''''''''''''''''''''''''''''''''''''''''" add sketch "Editable cross section (71)" along normal blind 6 separate body makes body 50 in component "left lift shelf 4"
sketch "Editable cross section (72)" plane through (0, 0, 0) normal (0, 0, 1) x (1, 0, 0) in component "left intake ramp"
  line L0 (-14, -2.5) -> (14, -2.5)
  line L1 (14, -2.5) -> (14, 2.5)
  line L2 (14, 2.5) -> (-14, 2.5)
  line L3 (-14, 2.5) -> (-14, -2.5)
extrude "Stock length''''''''''''''''''''''''''''''''''''''''''''''''''" add sketch "Editable cross section (72)" along normal blind 128.316 separate body makes body 51 in component "left intake ramp"
sketch "Editable cross section (73)" plane through (0, 0, 0) normal (0, 0, 1) x (1, 0, 0) in component "central fore-aft feed deck"
  line L0 (-239.5, -87) -> (239.5, -87)
  line L1 (239.5, -87) -> (239.5, 87)
  line L2 (239.5, 87) -> (-239.5, 87)
  line L3 (-239.5, 87) -> (-239.5, -87)
extrude "Stock length'''''''''''''''''''''''''''''''''''''''''''''''''''" add sketch "Editable cross section (73)" along normal blind 5 separate body makes body 52 in component "central fore-aft feed deck"
sketch "Editable cross section (74)" plane through (0, 0, 0) normal (0, 0, 1) x (1, 0, 0) in component "left lower lift stub shaft"
  circle A0 centre (0, 0) radius 7.5
extrude "Stock length''''''''''''''''''''''''''''''''''''''''''''''''''''" add sketch "Editable cross section (74)" along normal blind 28 separate body makes body 53 in component "left lower lift stub shaft"
sketch "Editable cross section (75)" plane through (0, 0, 0) normal (0, 0, 1) x (1, 0, 0) in component "right lower lift stub shaft"
  circle A0 centre (0, 0) radius 7.5
extrude "Stock length'''''''''''''''''''''''''''''''''''''''''''''''''''''" add sketch "Editable cross section (75)" along normal blind 28 separate body makes body 54 in component "right lower lift stub shaft"
sketch "Editable cross section (76)" plane through (0, 0, 0) normal (0, 0, 1) x (1, 0, 0) in component "left upper lift stub shaft"
  circle A0 centre (0, 0) radius 7.5
extrude "Stock length''''''''''''''''''''''''''''''''''''''''''''''''''''''" add sketch "Editable cross section (76)" along normal blind 28 separate body makes body 55 in component "left upper lift stub shaft"
sketch "Editable cross section (77)" plane through (0, 0, 0) normal (0, 0, 1) x (1, 0, 0) in component "right upper lift stub shaft"
  circle A0 centre (0, 0) radius 7.5
extrude "Stock length'''''''''''''''''''''''''''''''''''''''''''''''''''''''" add sketch "Editable cross section (77)" along normal blind 28 separate body makes body 56 in component "right upper lift stub shaft"
sketch "Editable cross section (78)" plane through (0, 0, 0) normal (0, 0, 1) x (1, 0, 0) in component "ground intake roller"
  circle A0 centre (0, 0) radius 38
extrude "Stock length''''''''''''''''''''''''''''''''''''''''''''''''''''''''" add sketch "Editable cross section (78)" along normal blind 252 separate body makes body 57 in component "ground intake roller"
sketch "Editable cross section (79)" plane through (0, 0, 0) normal (0, 0, 1) x (1, 0, 0) in component "right intake bearing arm"
  line L0 (-6, -7.5) -> (6, -7.5)
  line L1 (6, -7.5) -> (6, 7.5)
  line L2 (6, 7.5) -> (-6, 7.5)
  line L3 (-6, 7.5) -> (-6, -7.5)
extrude "Stock length'''''''''''''''''''''''''''''''''''''''''''''''''''''''''" add sketch "Editable cross section (79)" along normal blind 103 separate body makes body 58 in component "right intake bearing arm"
sketch "Editable cross section (80)" plane through (0, 0, 0) normal (0, 0, 1) x (1, 0, 0) in component "right intake pivot plate"
  line L0 (-6, -11) -> (6, -11)
  line L1 (6, -11) -> (6, 11)
  line L2 (6, 11) -> (-6, 11)
  line L3 (-6, 11) -> (-6, -11)
extrude "Stock length''''''''''''''''''''''''''''''''''''''''''''''''''''''''''" add sketch "Editable cross section (80)" along normal blind 40.6079 separate body makes body 59 in component "right intake pivot plate"
sketch "Editable cross section (81)" plane through (0, 0, 0) normal (0, 0, 1) x (1, 0, 0) in component "right intake pivot axle"
  circle A0 centre (0, 0) radius 6
extrude "Stock length'''''''''''''''''''''''''''''''''''''''''''''''''''''''''''" add sketch "Editable cross section (81)" along normal blind 50 separate body makes body 60 in component "right intake pivot axle"
sketch "Editable cross section (82)" plane through (0, 0, 0) normal (0, 0, 1) x (1, 0, 0) in component "right intake journal"
  circle A0 centre (0, 0) radius 7
extrude "Stock length''''''''''''''''''''''''''''''''''''''''''''''''''''''''''''" add sketch "Editable cross section (82)" along normal blind 24 separate body makes body 61 in component "right intake journal"
sketch "Editable cross section (83)" plane through (0, 0, 0) normal (0, 0, 1) x (1, 0, 0) in component "right upper head cheek"
  line L0 (-85, -4) -> (85, -4)
  line L1 (85, -4) -> (85, 4)
  line L2 (85, 4) -> (-85, 4)
  line L3 (-85, 4) -> (-85, -4)
extrude "Stock length'''''''''''''''''''''''''''''''''''''''''''''''''''''''''''''" add sketch "Editable cross section (83)" along normal blind 144 separate body makes body 62 in component "right upper head cheek"
sketch "Editable cross section (84)" plane through (0, 0, 0) normal (0, 0, 1) x (1, 0, 0) in component "left intake bearing arm"
  line L0 (-6, -7.5) -> (6, -7.5)
  line L1 (6, -7.5) -> (6, 7.5)
  line L2 (6, 7.5) -> (-6, 7.5)
  line L3 (-6, 7.5) -> (-6, -7.5)
extrude "Stock length''''''''''''''''''''''''''''''''''''''''''''''''''''''''''''''" add sketch "Editable cross section (84)" along normal blind 103 separate body makes body 63 in component "left intake bearing arm"
sketch "Editable cross section (85)" plane through (0, 0, 0) normal (0, 0, 1) x (1, 0, 0) in component "left intake pivot plate"
  line L0 (-6, -11) -> (6, -11)
  line L1 (6, -11) -> (6, 11)
  line L2 (6, 11) -> (-6, 11)
  line L3 (-6, 11) -> (-6, -11)
extrude "Stock length'''''''''''''''''''''''''''''''''''''''''''''''''''''''''''''''" add sketch "Editable cross section (85)" along normal blind 40.6079 separate body makes body 64 in component "left intake pivot plate"
sketch "Editable cross section (86)" plane through (0, 0, 0) normal (0, 0, 1) x (1, 0, 0) in component "left intake pivot axle"
  circle A0 centre (0, 0) radius 6
extrude "Stock length''''''''''''''''''''''''''''''''''''''''''''''''''''''''''''''''" add sketch "Editable cross section (86)" along normal blind 50 separate body makes body 65 in component "left intake pivot axle"
sketch "Editable cross section (87)" plane through (0, 0, 0) normal (0, 0, 1) x (1, 0, 0) in component "left intake journal"
  circle A0 centre (0, 0) radius 7
extrude "Stock length'''''''''''''''''''''''''''''''''''''''''''''''''''''''''''''''''" add sketch "Editable cross section (87)" along normal blind 24 separate body makes body 66 in component "left intake journal"
sketch "Editable cross section (88)" plane through (0, 0, 0) normal (0, 0, 1) x (1, 0, 0) in component "left upper head cheek"
  line L0 (-85, -4) -> (85, -4)
  line L1 (85, -4) -> (85, 4)
  line L2 (85, 4) -> (-85, 4)
  line L3 (-85, 4) -> (-85, -4)
extrude "Stock length''''''''''''''''''''''''''''''''''''''''''''''''''''''''''''''''''" add sketch "Editable cross section (88)" along normal blind 144 separate body makes body 67 in component "left upper head cheek"
sketch "Editable cross section (89)" plane through (0, 0, 0) normal (0, 0, 1) x (1, 0, 0) in component "right scoring wheel"
  circle A0 centre (0, 0) radius 32
extrude "Stock length'''''''''''''''''''''''''''''''''''''''''''''''''''''''''''''''''''" add sketch "Editable cross section (89)" along normal blind 50 separate body makes body 68 in component "right scoring wheel"
sketch "Editable cross section (90)" plane through (0, 0, 0) normal (0, 0, 1) x (1, 0, 0) in component "right scoring spindle"
  circle A0 centre (0, 0) radius 6
extrude "Stock length''''''''''''''''''''''''''''''''''''''''''''''''''''''''''''''''''''" add sketch "Editable cross section (90)" along normal blind 72 separate body makes body 69 in component "right scoring spindle"
sketch "Editable cross section (91)" plane through (0, 0, 0) normal (0, 0, 1) x (1, 0, 0) in component "right upper guide"
  line L0 (-3, -5) -> (3, -5)
  line L1 (3, -5) -> (3, 5)
  line L2 (3, 5) -> (-3, 5)
  line L3 (-3, 5) -> (-3, -5)
extrude "Stock length'''''''''''''''''''''''''''''''''''''''''''''''''''''''''''''''''''''" add sketch "Editable cross section (91)" along normal blind 203.3249 separate body makes body 70 in component "right upper guide"
sketch "Editable cross section (92)" plane through (0, 0, 0) normal (0, 0, 1) x (1, 0, 0) in component "right scoring bearing bridge -33"
  line L0 (-7.5, -5) -> (7.5, -5)
  line L1 (7.5, -5) -> (7.5, 5)
  line L2 (7.5, 5) -> (-7.5, 5)
  line L3 (-7.5, 5) -> (-7.5, -5)
extrude "Stock length''''''''''''''''''''''''''''''''''''''''''''''''''''''''''''''''''''''" add sketch "Editable cross section (92)" along normal blind 42 separate body makes body 71 in component "right scoring bearing bridge -33"
sketch "Editable cross section (93)" plane through (0, 0, 0) normal (0, 0, 1) x (1, 0, 0) in component "right scoring bearing bridge 33"
  line L0 (-7.5, -5) -> (7.5, -5)
  line L1 (7.5, -5) -> (7.5, 5)
  line L2 (7.5, 5) -> (-7.5, 5)
  line L3 (-7.5, 5) -> (-7.5, -5)
extrude "Stock length'''''''''''''''''''''''''''''''''''''''''''''''''''''''''''''''''''''''" add sketch "Editable cross section (93)" along normal blind 42 separate body makes body 72 in component "right scoring bearing bridge 33"
sketch "Editable cross section (94)" plane through (0, 0, 0) normal (0, 0, 1) x (1, 0, 0) in component "left scoring wheel"
  circle A0 centre (0, 0) radius 32
extrude "Stock length''''''''''''''''''''''''''''''''''''''''''''''''''''''''''''''''''''''''" add sketch "Editable cross section (94)" along normal blind 50 separate body makes body 73 in component "left scoring wheel"
sketch "Editable cross section (95)" plane through (0, 0, 0) normal (0, 0, 1) x (1, 0, 0) in component "left scoring spindle"
  circle A0 centre (0, 0) radius 6
extrude "Stock length'''''''''''''''''''''''''''''''''''''''''''''''''''''''''''''''''''''''''" add sketch "Editable cross section (95)" along normal blind 72 separate body makes body 74 in component "left scoring spindle"
sketch "Editable cross section (96)" plane through (0, 0, 0) normal (0, 0, 1) x (1, 0, 0) in component "left upper guide"
  line L0 (-3, -5) -> (3, -5)
  line L1 (3, -5) -> (3, 5)
  line L2 (3, 5) -> (-3, 5)
  line L3 (-3, 5) -> (-3, -5)
extrude "Stock length''''''''''''''''''''''''''''''''''''''''''''''''''''''''''''''''''''''''''" add sketch "Editable cross section (96)" along normal blind 203.3249 separate body makes body 75 in component "left upper guide"
sketch "Editable cross section (97)" plane through (0, 0, 0) normal (0, 0, 1) x (1, 0, 0) in component "left scoring bearing bridge -33"
  line L0 (-7.5, -5) -> (7.5, -5)
  line L1 (7.5, -5) -> (7.5, 5)
  line L2 (7.5, 5) -> (-7.5, 5)
  line L3 (-7.5, 5) -> (-7.5, -5)
extrude "Stock length'''''''''''''''''''''''''''''''''''''''''''''''''''''''''''''''''''''''''''" add sketch "Editable cross section (97)" along normal blind 42 separate body makes body 76 in component "left scoring bearing bridge -33"